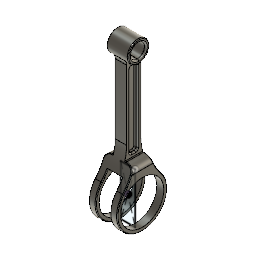
fork connecting rod v2 (Autodesk Fusion 360 design; units mm, degrees)
Autodesk Fusion 360 part; units mm, degrees
sketch "Sketch1" plane through (0, 0, 0) normal (1, 0, 0) x (0, 1, 0)
  circle A0 centre (0, 180) radius 10
  circle A1 centre (0, 0) radius 25
  circle A2 centre (0, 0) radius 30
  line L0 (-0.0071, 170) -> (0.0071, 170)
  line L1 (10.2253, 165.3052) -> (10.2253, 67.7414)
  line L2 (-10, 68.0074) -> (-10, 165)
  line L3 (0, 0) -> (0, 30)
  arc A3 (-26.6667, 22.6691) -> (26.7418, 22.5805) centre (0, 0) ccw
  arc A4 (10.2253, 67.7414) -> (26.7418, 22.5805) centre (80.2253, 67.7414) ccw
  arc A5 (-26.6667, 22.6691) -> (-10, 68.0074) centre (-80, 68.0074) ccw
  arc A6 (12.1352, 171.1831) -> (10.2253, 165.3052) centre (20.2253, 165.3052) ccw
  arc A7 (-10, 165) -> (-12, 171) centre (-20, 165) ccw
  line L4 (-12.3703, 49.9456) -> (12.5252, 49.9456)
  arc A8 (-26.6667, 22.6691) -> (26.7418, 22.5805) centre (0, 0) ccw
  circle A9 centre (0, 180) radius 15
  line L5 (-2.5, 160) -> (2.5, 160)
  line L6 (5, 157.5) -> (5, 57.5)
  line L7 (2.5, 55) -> (-2.5, 55)
  line L8 (-5, 57.5) -> (-5, 157.5)
  arc A10 (5, 157.5) -> (2.5, 160) centre (2.5, 157.5) ccw
  arc A11 (-2.5, 160) -> (-5, 157.5) centre (-2.5, 157.5) ccw
  arc A12 (-5, 57.5) -> (-2.5, 55) centre (-2.5, 57.5) ccw
  arc A13 (2.5, 55) -> (5, 57.5) centre (2.5, 57.5) ccw
  dimension "d1" = 180
  dimension "d3" = 20
  dimension "d4" = 70
  dimension "d5" = 50
  dimension "d6" = 60
  dimension "d7" = 70
  dimension "d8" = 70
  dimension "d9" = 10
  dimension "d10" = 10
  dimension "d11" = 70
  dimension "d20" = 30
  dimension "d51" = 2.5
  constraint coincident A1.centre A2.centre
  constraint vertical L3
  constraint concentric A2 A3
  constraint horizontal L0
  constraint vertical L1
  constraint vertical L2
  constraint coincident A0 L0.end
  constraint coincident A0 L0.start
  constraint coincident A2 L3.end
  constraint tangent A3 A4
  constraint tangent L1 A4
  constraint tangent A3 A5
  constraint tangent L2 A5
  constraint tangent L1 A6
  constraint tangent L2 A7
  constraint concentric A2 A8
  constraint coincident A5 L4.start
  constraint coincident A4 L4.end
  constraint concentric A0 A9
  constraint tangent A6 A9
  constraint tangent A7 A9
  constraint horizontal L5
  constraint vertical L6
  constraint horizontal L7
  constraint vertical L8
  constraint tangent L5 A10
  constraint tangent L6 A10
  constraint tangent L5 A11
  constraint tangent L8 A11
  constraint equal A10 A11
  constraint tangent L7 A12
  constraint tangent L8 A12
  constraint equal A10 A12
  constraint tangent L6 A13
  constraint tangent L7 A13
  constraint equal A10 A13
  measures "d1" distance of A1.centre A0.centre
  measures "d3" diameter of A0
  measures "d4" diameter of A3
  measures "d5" diameter of A1
  measures "d6" diameter of A2
  measures "d7" radius of A4
  measures "d8" radius of A5
  measures "d9" radius of A6
  measures "d10" radius of A7
  measures "d11" diameter of A8
  measures "d20" diameter of A9
  measures "d51" radius of A10
extrude "Extrude1" add sketch "Sketch1" along normal mid plane 40 contours A3 A4 A5 L4 A8 makes body 1
extrude "Extrude2" add sketch "Sketch1" along normal mid plane 16 contours L1 L2 A4 A5 A6 A7 L4 A9 | L5 L6 L7 L8 A10 A11 A12 A13 bodies 1
sketch "Sketch2" plane through (0, 0, 0) normal (0, 1, 0) x (1, 0, 0)
  line L0 (10, 35) -> (-10, 35)
  line L1 (-10, 35) -> (-10, -35)
  line L2 (-10, -35) -> (10, -35)
  line L3 (10, -35) -> (10, 35)
  line L4 (10, 35) -> (-10, -35) construction
  line L5 (-10, 35) -> (10, -35) construction
  line L6 (-10, -35) -> (10, -35)
  dimension "d16" = 20
  dimension "d17" = 70
  constraint horizontal L0
  constraint perpendicular L0 L1
  constraint parallel L0 L2
  constraint parallel L1 L3
  constraint coincident L4 origin
  constraint coincident L5 origin
  constraint horizontal L6
  measures "d16" distance of L1.end L2.end
  measures "d17" distance of L0.end L1.end
extrude "Extrude3" cut sketch "Sketch2" along normal mid plane 120 bodies 1
extrude "Extrude4" add sketch "Sketch1" along normal mid plane 30 separate body contours A9 makes body 2
extrude "Extrude5" cut sketch "Sketch2" along normal mid plane 70 bodies 1
combine "Combine1" operation add target body 1 tool bodies 2
extrude "Extrude6" cut sketch "Sketch1" against normal blind 5 from surface at 8 contours L5 L6 L7 L8 A10 A11 A12 A13 bodies 1
extrude "Extrude7" cut sketch "Sketch1" along normal blind 5 from surface at -8 contours L5 L6 L7 L8 A10 A11 A12 A13 bodies 1
fillet "Fillet1" radius 10 2 edges at (20, 0.0774, 49.9456) (-20, 0.0774, 49.9456) on bodies 1
fillet "Fillet2" radius 2 4 edges at (15, 3.6162, 189.3233) (15, 0, 170) (-15, -3.6162, 189.3233) (-15, 0, 170) on bodies 1
fillet "Fillet3" radius 1 2 edges at (15, -13.9849, 174.5758) (-15, -13.9849, 185.4242) on bodies 1
fillet "Fillet4" radius 2 8 edges at (-8, 0, 55) (-8, 4.2678, 55.7322) (-8, 5, 107.5) (-8, 4.2678, 159.2678) (-8, 0, 160) (-8, -4.2678, 159.2678) (-8, -5, 107.5) (-8, -4.2678, 55.7322) on bodies 1
fillet "Fillet5" radius 2 8 edges at (8, 0, 55) (8, -4.2678, 55.7322) (8, -5, 107.5) (8, -4.2678, 159.2678) (8, 0, 160) (8, 4.2678, 159.2678) (8, 5, 107.5) (8, 4.2678, 55.7322) on bodies 1
fillet "Fillet6" radius 1 3 edges at (-10, 22.2148, 28.5651) (-10, -0.0581, -35) (-10, -22.1392, 28.6103) on bodies 1
fillet "Fillet7" radius 1 3 edges at (10, -22.1392, 28.6103) (10, -0.0581, -35) (10, 22.2148, 28.5651) on bodies 1
fillet "Fillet8" radius 1 7 edges at (9, -12.3703, 49.9456) (17.1928, -13.2605, 46.8925) (20, -20.6369, 30.9125) (20, -0.0581, -35) (20, 20.7242, 30.8684) (17.1902, 13.4014, 46.8953) (9, 12.5252, 49.9456) on bodies 1
fillet "Fillet9" radius 1 7 edges at (-9, 12.5252, 49.9456) (-17.1902, 13.4014, 46.8953) (-20, 20.7242, 30.8684) (-20, -0.0581, -35) (-20, -20.6369, 30.9125) (-17.1928, -13.2605, 46.8925) (-9, -12.3703, 49.9456) on bodies 1
